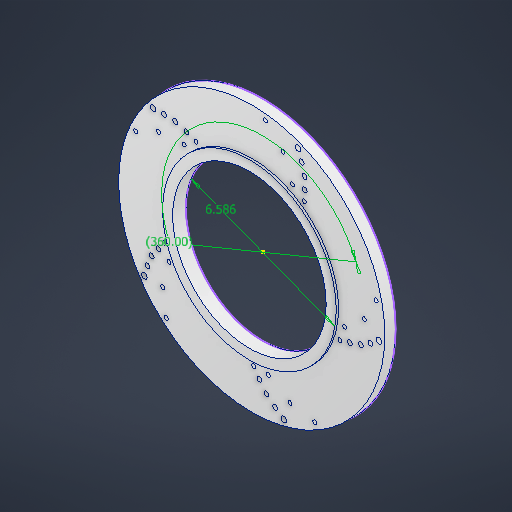
# Autodesk Inventor part: disk back mod
Saved by Autodesk Inventor 2027 (Build 310192060, 192F)
## iProperties
Created: 2026-06-30
Part Number: disk back mod
Material: Aluminum 6061
Document SubType Name: Modeling
Designer: ElieH
Density: 2.7 g/cm^3
Appearance: Aluminum - Flat
Author: ElieH
Autodesk Inventor part; units mm, degrees
ref_plane "YZ Plane" through (0, 0, 0) normal (1, 0, 0) x (0, 1, 0)
ref_plane "XZ Plane" through (0, 0, 0) normal (0, 1, 0) x (-1, 0, 0)
ref_plane "XY Plane" through (0, 0, 0) normal (0, 0, 1) x (1, 0, 0)
sketch "Sketch1" plane through (0, 0, 0) normal (0, 0, 1) x (1, 0, 0)
  circle A0 centre (-0.2006, 0.0752) radius 145.0085
  circle A1 centre (-0.2006, 0.0752) radius 94.6473
  circle A2 centre (-109.2515, -52.077) radius 2.6413
  circle A3 centre (-117.1886, -74.729) radius 3.0815
  circle A4 centre (-113.7656, -63.5763) radius 2.6413
  circle A5 centre (-101.9641, -41.6897) radius 2.6413
  circle A6 centre (-95.0692, -33.0157) radius 2.2011
  circle A7 centre (-90.2829, -48.2233) radius 2.2011
  circle A8 centre (-97.01, -75.3092) radius 2.2011
  circle A9 centre (-93.2517, -102.5534) radius 2.2011
  circle A10 centre (-0.2006, 0.0752) radius 83.6422
  circle A11 centre (8.0736, -109.6137) radius 2.6413
  circle A12 centre (15.7005, -119.7543) radius 2.6413
  circle A13 centre (25.2421, -127.6009) radius 2.6413
  circle A14 centre (34.7912, -134.3027) radius 3.0815
  circle A15 centre (17.8971, -100.5232) radius 2.2011
  circle A16 centre (1.9547, -100.3758) radius 2.2011
  circle A17 centre (41.5785, -115.291) radius 2.2011
  circle A18 centre (68.6506, -120.1357) radius 2.2011
  circle A19 centre (106.6767, -25.9513) radius 2.6413
  circle A20 centre (118.6778, -21.8313) radius 2.6413
  circle A21 centre (129.0889, -15.1814) radius 2.6413
  circle A22 centre (138.4135, -8.1707) radius 3.0815
  circle A23 centre (101.0667, -13.7995) radius 2.2011
  circle A24 centre (96.0001, -28.916) radius 2.2011
  circle A25 centre (122.4297, 4.1593) radius 2.2011
  circle A26 centre (135.4029, 28.4094) radius 2.2011
  circle A27 centre (57.579, 93.6789) radius 2.6413
  circle A28 centre (57.3692, 106.3658) radius 2.6413
  circle A29 centre (54.262, 118.3222) radius 2.6413
  circle A30 centre (50.4759, 129.3569) radius 3.0815
  circle A31 centre (44.2884, 92.0986) radius 2.2011
  circle A32 centre (57.0994, 82.6087) radius 2.2011
  circle A33 centre (33.81, 117.9656) radius 2.2011
  circle A34 centre (14.7558, 137.7976) radius 2.2011
  circle A35 centre (-71.3681, 83.952) radius 2.6413
  circle A36 centre (-83.4989, 87.6729) radius 2.6413
  circle A37 centre (-95.8303, 88.4125) radius 2.6413
  circle A38 centre (-107.4949, 88.2216) radius 3.0815
  circle A39 centre (-73.9722, 70.8235) radius 2.2011
  circle A40 centre (-60.9879, 80.075) radius 2.2011
  circle A41 centre (-101.8111, 68.8514) radius 2.2011
  circle A42 centre (-126.5605, 56.8582) radius 2.2011
  point P0 (0, 0)
  dimension "d7" = 360
  dimension "d11" = 167.2844
  constraints: 43 centre point, 1 coincident, 81 other
  measures "d11" diameter of A10
extrude "Extrusion2" add sketch "Sketch1" along normal blind 14.375 contours A1
extrude "Extrusion3" add sketch "Sketch1" along normal blind 11.875 contours A0
body "Solid1"
